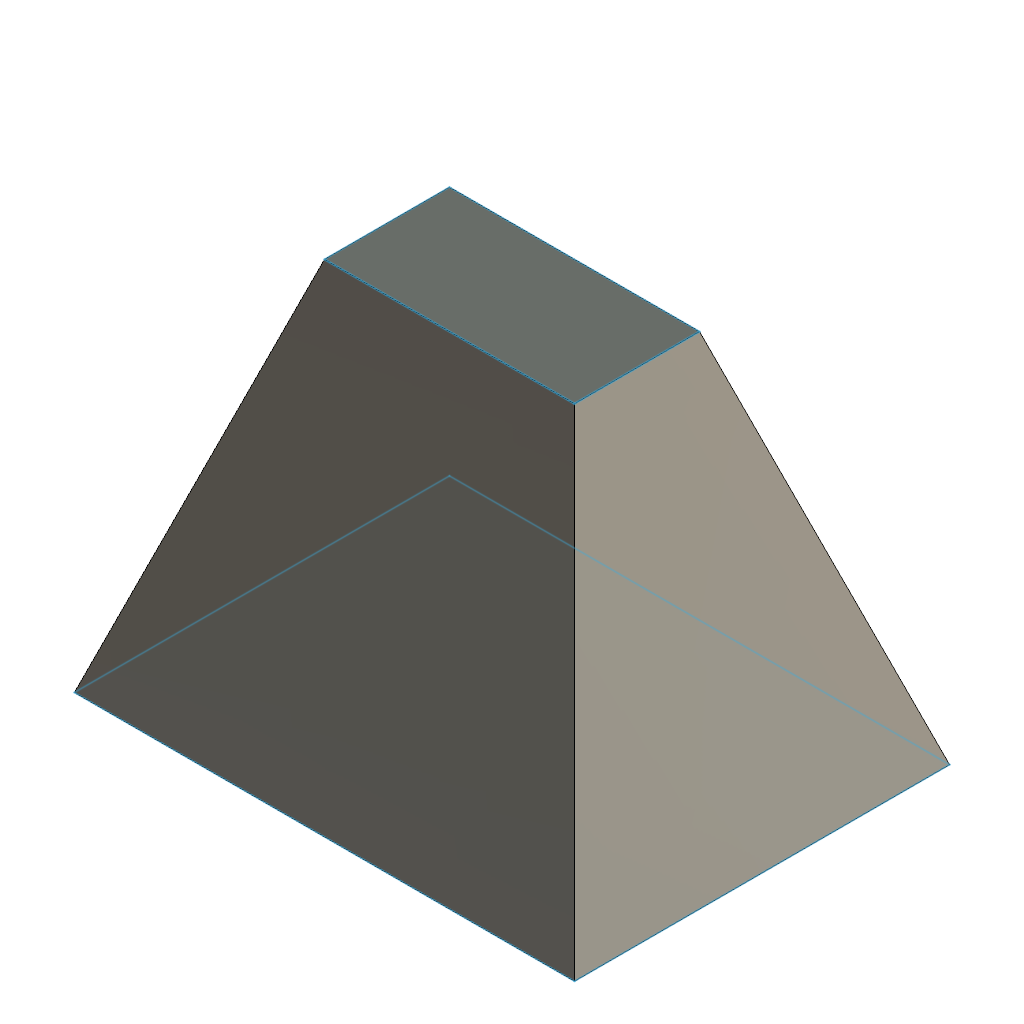
LoftRects (Autodesk Fusion 360 design; units mm, degrees)
part number: 2026-11-12-20-32-23-654
Autodesk Fusion 360 part; units mm, degrees
sketch "Loft base" plane through (0, 0, 0) normal (0, 0, 1) x (1, 0, 0)
  line L0 (0, 0) -> (40, 0)
  line L1 (40, 0) -> (40, 30)
  line L2 (40, 30) -> (0, 30)
  line L3 (0, 30) -> (0, 0)
ref_plane "WorkPlane1" through (0, 0, 30) normal (0, 0, 1) x (1, 0, 0)
sketch "Loft top" plane through (0, 0, 30) normal (0, 0, 1) x (1, 0, 0)
  line L0 (10, 10) -> (30, 10)
  line L1 (30, 10) -> (30, 20)
  line L2 (30, 20) -> (10, 20)
  line L3 (10, 20) -> (10, 10)
loft "Block loft" add profiles "Loft base", "Loft top" section 1 section 2
